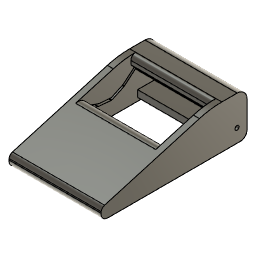
kb46sp_r1 (Autodesk Fusion 360 design; units mm, degrees)
Autodesk Fusion 360 part; units mm, degrees
sketch "Sketch10" plane through (0, 0, 0) normal (1, 0, 0) x (0, 1, 0)
  line L0 (-37.4967, 30.9274) -> (-28.9967, 45.6498)
  line L1 (-28.9967, 45.6498) -> (28.9967, 45.6498)
  line L2 (-37.4967, 30.9274) -> (-20.4967, 30.9274) construction
  line L3 (37.4967, 30.9274) -> (55.3527, 0)
  line L4 (37.4967, 30.9274) -> (28.9967, 45.6498)
  line L5 (-37.4967, 30.9274) -> (-55.3527, 0)
  line L6 (-37.4967, 30.9274) -> (-20.4967, 30.9274) construction
  line L7 (-28.9967, 45.6498) -> (28.9967, 45.6498)
  line L8 (-37.4967, 30.9274) -> (-28.9967, 45.6498)
  line L9 (-37.4967, 30.9274) -> (-55.3527, 0)
  line L10 (37.4967, 30.9274) -> (55.3527, 0)
  line L11 (37.4967, 30.9274) -> (28.9967, 45.6498)
  line L12 (55.3527, 0) -> (-55.3527, 0)
  line L13 (0, 0) -> (0, 45.6498) construction
  dimension "d62" = 17
  dimension "d63" = 60
  dimension "d64" = 17
  dimension "d66" = 17
  dimension "d67" = 60
  dimension "d68" = 17
  constraint horizontal L2
  constraint horizontal L6
  constraint horizontal L12
  constraint midpoint L12 L13.start
  constraint midpoint L7 L13.end
  constraint perpendicular L7 L13
  measures "d62" distance of L1.end L3.start
  measures "d63" angle of L2 L8
  measures "d64" distance of L0.start L0.end
  measures "d66" distance of L1.end L3.start
  measures "d67" angle of L0 L6
  measures "d68" distance of L0.end L0.start
sketch "Sketch12" plane through (0, 0, 0) normal (1, 0, 0) x (0, 1, 0)
  line L0 (0, 0) -> (-220, 0)
  line L1 (-55, 65) -> (0, 65)
  line L2 (0, 65) -> (0, 0)
  line L3 (-55, 65) -> (-218.051, 17.5974)
  line L4 (-220, 0) -> (-218.051, 17.5974)
  dimension "d39" = 65
  dimension "d41" = 55
  dimension "d197" = 220
  constraint vertical L2
  constraint coincident L0.start L2.end
  constraint horizontal L0
  measures "d39" distance of L0 L1
  measures "d41" distance of L1.start L1.end
  measures "d197" distance of L0.start L0.end
extrude "Extrude6" add sketch "Sketch12" along normal mid plane 138 makes body 1
sketch "Sketch14" plane through (0, 0, 0) normal (1, 0, 0) x (0, 1, 0)
  line L0 (-18.4009, 19.9024) -> (0, 14.9719)
  line L1 (-0.9059, 11.5911) -> (-19.3068, 16.5216)
  line L2 (-18.4009, 19.9024) -> (-40.8742, 32.8774)
  line L3 (-43.5589, 34.4274) -> (-45.3089, 31.3963)
  line L4 (-42.6242, 29.8463) -> (-20.1509, 16.8713)
  line L5 (18.4009, 19.9024) -> (0, 14.9719)
  line L6 (0.9059, 11.5911) -> (19.3068, 16.5216)
  line L7 (40.8742, 32.8774) -> (18.4009, 19.9024)
  line L8 (45.3089, 31.3963) -> (43.5589, 34.4274)
  line L9 (20.1509, 16.8713) -> (42.6242, 29.8463)
  line L10 (0, 14.9719) -> (0, 0) construction
  line L11 (20.1509, 16.8713) -> (19.3068, 16.5216)
  line L12 (0.9059, 11.5911) -> (0.4529, 11.4697)
  line L13 (0.4529, 11.4697) -> (-0.9059, 11.5911)
  line L14 (-19.3068, 16.5216) -> (-20.1509, 16.8713)
  arc A0 (-40.8742, 32.8774) -> (-43.5589, 34.4274) centre (-42.2166, 33.6524) ccw
  arc A1 (-45.3089, 31.3963) -> (-42.6242, 29.8463) centre (-43.9666, 30.6213) ccw
  arc A2 (43.5589, 34.4274) -> (40.8742, 32.8774) centre (42.2166, 33.6524) ccw
  arc A3 (42.6242, 29.8463) -> (45.3089, 31.3963) centre (43.9666, 30.6213) ccw
  dimension "d104" = 3.1
  dimension "d105" = 3.1
  dimension "d106" = 3.1
  dimension "d107" = 3.1
  constraint parallel L0 L1
  constraint perpendicular L2 L3
  constraint parallel L2 L4
  constraint parallel L5 L6
  constraint parallel L7 L9
  constraint vertical L10
  measures "d104" diameter of A2
  measures "d105" diameter of A3
  measures "d106" diameter of A0
  measures "d107" diameter of A1
extrude "Extrude9" add sketch "Sketch14" along normal mid plane 130 separate body makes body 2
extrude "Extrude10" add sketch "Sketch10" along normal mid plane 120 separate body makes body 3
move_body "Move20" bodies 3 2 to x (1, 0, 0) y (0, 0.984808, 0.173648) z (0, -0.173648, 0.984808) at (0, -0.8409, 9.6119)
move_body "Move21" bodies 3 2 to x (1, 0, 0) y (0, 1, 0) z (0, 0, 1) at (0, -70.951, 0)
sketch "Sketch16" plane through (0, 0, 0) normal (1, 0, 0) x (0, 1, 0)
  line L0 (-45, 71.5447) -> (-108.2752, 71.5447)
  line L1 (-40.2353, 46.5806) -> (-37.2477, 49.0875)
  line L2 (-34.873, 51.0801) -> (-32.6233, 48.399)
  line L3 (-34.998, 46.4063) -> (-37.9856, 43.8995)
  line L4 (-113.4492, 38.646) -> (-115.1593, 33.9475)
  line L5 (-120.6684, 35.9493) -> (-121.8644, 32.6634)
  line L6 (-118.9514, 31.6031) -> (-116.3564, 30.6586)
  line L7 (-10, 40.0693) -> (-10, 15)
  line L8 (-10, 15) -> (-35, 15)
  line L9 (-37.9856, 43.8995) -> (-34.998, 46.4063)
  line L10 (-37.2477, 49.0875) -> (-40.2353, 46.5806)
  line L11 (-118.9514, 31.6031) -> (-116.3564, 30.6586)
  line L12 (-34.7716, 40.0693) -> (-37.9856, 43.8995)
  line L13 (-45, 71.5447) -> (-45, 52.2589)
  line L14 (-40.2353, 46.5806) -> (-45, 52.2589)
  line L15 (-10, 40.0693) -> (-34.7716, 40.0693)
  line L16 (-119.7766, 21.2617) -> (-144.7766, 21.2617)
  line L17 (-116.3564, 30.6586) -> (-119.7766, 21.2617)
  line L18 (-144.7766, 4.9542) -> (-148.678, 4.9542)
  line L19 (-151.7766, 5) -> (-151.7766, 0)
  line L20 (-144.7766, 21.2617) -> (-144.7766, 4.9542)
  line L21 (-35, 5) -> (-31.1, 5)
  line L22 (-28, 5) -> (-28, 0)
  line L23 (-35, 15) -> (-35, 5)
  line L24 (-151.7766, 0) -> (-28, 0)
  line L25 (-117.7543, 34.892) -> (-115.1593, 33.9475)
  arc A0 (-148.678, 4.9542) -> (-151.7766, 4.8729) centre (-150.2279, 4.9365) ccw
  arc A1 (-28, 5) -> (-31.1, 5) centre (-29.55, 5) ccw
  arc A2 (-34.998, 46.4063) -> (-32.6233, 48.399) centre (-33.8106, 47.4027) ccw
  arc A3 (-34.873, 51.0801) -> (-37.2477, 49.0875) centre (-36.0604, 50.0838) ccw
  arc A4 (-117.7543, 34.892) -> (-120.6684, 35.9493) centre (-119.2119, 35.4192) ccw
  arc A5 (-121.8644, 32.6634) -> (-118.9514, 31.6031) centre (-120.4079, 32.1332) ccw
  line L26 (-113.4492, 38.646) -> (-121.4288, 48.1557)
  line L27 (-113.4492, 38.646) -> (-103.1508, 38.646) construction
  line L28 (-121.4288, 48.1557) -> (-108.2752, 71.5447)
  dimension "d74" = 10
  dimension "d75" = 5
  dimension "d77" = 15
  dimension "d78" = 25
  dimension "d79" = 10
  dimension "d81" = 7
  dimension "d82" = 5
  dimension "d83" = 7
  dimension "d84" = 5
  dimension "d110" = 25
  dimension "d118" = 3.1
  dimension "d119" = 3.1
  dimension "d120" = 3.1
  dimension "d121" = 3.1
  dimension "d122" = 3.1
  dimension "d123" = 3.1
  dimension "d198" = 130
  dimension "d199" = 5
  dimension "d200" = 3.5
  dimension "d201" = 3.5
  constraint coincident L2.end A2.end
  constraint coincident L5.end A5.start
  constraint perpendicular L7 L8
  constraint horizontal L0
  constraint perpendicular L3 L12
  constraint vertical L13
  constraint perpendicular L2 L9
  constraint perpendicular L2 L10
  constraint perpendicular L1 L14
  constraint perpendicular L7 L15
  constraint perpendicular L6 L17
  constraint perpendicular L18 L20
  constraint perpendicular L21 L23
  constraint perpendicular L22 L24
  constraint horizontal L16
  constraint coincident L19.start A0
  constraint perpendicular L4 L25
  constraint coincident L19 A0.end
  constraint vertical L20
  constraint vertical L19
  constraint vertical L7
  constraint vertical L23
  constraint vertical L22
  constraint horizontal L27
  constraint equal L6 L25
  constraint parallel L4 L17
  measures "d74" distance of origin L7
  measures "d75" distance of L3.end L12.start
  measures "d77" distance of origin L8
  measures "d78" distance of L7.end L8.end
  measures "d79" distance of L6.end L16.start
  measures "d81" horizontal distance of L18.start L19.start
  measures "d82" distance of L19.start L19.end
  measures "d83" distance of L21.start L22.start
  measures "d84" distance of L22.start L22.end
  measures "d110" horizontal distance of L16.start L16.end
  measures "d118" diameter of A1
  measures "d119" diameter of A0
  measures "d120" diameter of A3
  measures "d121" diameter of A2
  measures "d122" diameter of A4
  measures "d123" diameter of A5
  measures "d198" angle of L26 L27
  measures "d199" distance of L4.end L4.start
  measures "d200" distance of L6 L25
  measures "d201" distance of L3 L10
extrude "Extrude11" cut sketch "Sketch16" along normal mid plane 120 bodies 1
combine "Combine1" operation cut target body 1 tool bodies 2
fillet "Fillet1" radius 120 2 edges at (64.5, -55, 65) (-64.5, -55, 65) on bodies 1
fillet "Fillet2" radius 7 1 edges at (0, -45, 64.7904) on bodies 1
fillet "Fillet3" radius 7 1 edges at (0, -218.051, 17.5974) on bodies 1
fillet "Fillet4" radius 10 1 edges at (0, -220, 0) on bodies 1
fillet "Fillet5" radius 15 1 edges at (0, 0, 65) on bodies 1
fillet "Fillet6" radius 13 1 edges at (0, -119.764, 46.1716) on bodies 1
fillet "Fillet7" radius 10 1 edges at (0, 0, 0) on bodies 1
fillet "Fillet8" radius 3 2 edges at (0, -28, 0) (0, -151.7766, 0) on bodies 1
extrude "Extrude12" add sketch "Sketch14" along normal mid plane 130 separate body makes body 4
move_body "Move22" bodies 4 to x (1, 0, 0) y (0, 0.984808, 0.173648) z (0, -0.173648, 0.984808) at (0, 1.3002, 8.0781)
move_body "Move23" bodies 4 to x (1, 0, 0) y (0, 1, 0) z (0, 0, 1) at (65, -73.0932, 1.5308)
move_body "Move24" bodies 4 to x (1, 0, 0) y (0, 1, 0) z (0, 0, 1) at (-65, 0, 0)
combine "Combine2" operation cut target body 1 tool bodies 4
sketch "Sketch19" plane through (0, 0, 0) normal (1, 0, 0) x (0, 1, 0)
  line L0 (-134.6766, 21.2617) -> (-131.8766, 21.2617)
  line L1 (-128.7766, 21.2617) -> (-128.7766, 31.2617)
  line L2 (-131.8766, 31.2617) -> (-134.6766, 31.2617)
  line L3 (-137.7766, 31.2617) -> (-137.7766, 21.2617)
  arc A0 (-134.6766, 31.2617) -> (-137.7766, 31.2617) centre (-136.2266, 31.2617) ccw
  arc A1 (-128.7766, 31.2617) -> (-131.8766, 31.2617) centre (-130.3266, 31.2617) ccw
  arc A2 (-137.7766, 21.2617) -> (-134.6766, 21.2617) centre (-136.2266, 21.2617) ccw
  arc A3 (-131.8766, 21.2617) -> (-128.7766, 21.2617) centre (-130.3266, 21.2617) ccw
  line L4 (-10, 40.0693) -> (-34.7716, 40.0693) construction
  line L5 (-26, 40.0693) -> (-26, 55.0693)
  line L6 (-22.9, 55.0693) -> (-20.1, 55.0693)
  line L7 (-17, 55.0693) -> (-17, 40.0693)
  arc A4 (-22.9, 55.0693) -> (-26, 55.0693) centre (-24.45, 55.0693) ccw
  arc A5 (-17, 55.0693) -> (-20.1, 55.0693) centre (-18.55, 55.0693) ccw
  arc A6 (-20.1, 40.0693) -> (-17, 40.0693) centre (-18.55, 40.0693) ccw
  arc A7 (-26, 40.0693) -> (-22.9, 40.0693) centre (-24.45, 40.0693) ccw
  line L8 (-22.9, 40.0693) -> (-20.1, 40.0693)
  line L9 (0, 0) -> (-220, 0) construction
  line L10 (-205, 0) -> (-205, 41.8728) construction
  line L11 (-205, 0) -> (-196, 0)
  line L12 (-196, 0) -> (-196, 15)
  line L13 (-199.1, 15) -> (-201.9, 15)
  line L14 (-205, 15) -> (-205, 0)
  arc A8 (-196, 15) -> (-199.1, 15) centre (-197.55, 15) ccw
  arc A9 (-201.9, 15) -> (-205, 15) centre (-203.45, 15) ccw
  line L15 (-21, 0) -> (-12, 0)
  line L16 (-12, 0) -> (-12, 10)
  line L17 (-15.1, 10) -> (-17.9, 10)
  line L18 (-21, 10) -> (-21, 0)
  arc A10 (-17.9, 10) -> (-21, 10) centre (-19.45, 10) ccw
  arc A11 (-12, 10) -> (-15.1, 10) centre (-13.55, 10) ccw
  point P0 (-10, 40.0693)
  point P1 (-144.7766, 21.2617)
  dimension "d124" = 9
  dimension "d125" = 10
  dimension "d126" = 3.1
  dimension "d127" = 3.1
  dimension "d128" = 3.1
  dimension "d130" = 3.1
  dimension "d152" = 9
  dimension "d153" = 15
  dimension "d154" = 3.1
  dimension "d155" = 3.1
  dimension "d156" = 3.1
  dimension "d157" = 3.1
  dimension "d158" = 15
  dimension "d159" = 9
  dimension "d160" = 15
  dimension "d161" = 3.1
  dimension "d162" = 3.1
  dimension "d165" = 9
  dimension "d166" = 10
  dimension "d167" = 12
  dimension "d168" = 3.1
  dimension "d169" = 3.1
  dimension "d172" = 7
  dimension "d173" = 7
  constraint horizontal L0
  constraint vertical L1
  constraint horizontal L2
  constraint vertical L3
  constraint vertical L5
  constraint horizontal L6
  constraint vertical L7
  constraint coincident L7.end A6.end
  constraint coincident L4 A6.start
  constraint coincident L4 A7.end
  constraint coincident L9 L10.start
  constraint perpendicular L9 L10
  constraint horizontal L11
  constraint vertical L12
  constraint horizontal L13
  constraint vertical L14
  constraint horizontal L15
  constraint vertical L16
  constraint horizontal L17
  constraint vertical L18
  constraint coincident L9 L15.start
  measures "d124" distance of L3.end L1.start
  measures "d125" distance of L3.end L3.start
  measures "d126" diameter of A0
  measures "d127" diameter of A1
  measures "d128" diameter of A2
  measures "d130" diameter of A3
  measures "d152" distance of L7.end L5.start
  measures "d153" distance of L7.end L7.start
  measures "d154" diameter of A5
  measures "d155" diameter of A4
  measures "d156" diameter of A7
  measures "d157" diameter of A6
  measures "d158" distance of L9.end L10
  measures "d159" distance of L10.start L11.end
  measures "d160" distance of L10.start L14.start
  measures "d161" diameter of A9
  measures "d162" diameter of A8
  measures "d165" distance of L15.start L15.end
  measures "d166" distance of L15.start L18.start
  measures "d167" distance of L16 L9.start
  measures "d168" diameter of A11
  measures "d169" diameter of A10
  measures "d172" distance of L7 P0
  measures "d173" distance of L3 P1
extrude "Extrude13" cut sketch "Sketch19" along normal mid plane 130 bodies 1
sketch "Sketch21" plane through (0, 0, 0) normal (0, 1, 0) x (1, 0, 0)
  line L0 (-54, -22.1) -> (-54, -17) construction
  line L1 (-54, -17) -> (-42, -17)
  line L2 (-42, -17) -> (-42, -22.2)
  line L3 (-42, -22.2) -> (-54, -22.2)
  line L4 (-54, -22.2) -> (-54, -17)
  point P0 (-60, -15)
  dimension "d183" = 2
  dimension "d184" = 6
  dimension "d185" = 12
  dimension "d186" = 5.2
  constraint horizontal L1
  constraint vertical L2
  constraint horizontal L3
  constraint vertical L4
  measures "d183" vertical distance of L0.end P0
  measures "d184" horizontal distance of L0.end P0
  measures "d185" distance of L0.end L1.end
  measures "d186" distance of L0.end L3.end
extrude "Extrude14" cut sketch "Sketch21" against normal blind 30 bodies 1
sketch "Sketch23" plane through (0, 0, 0) normal (1, 0, 0) x (0, 1, 0)
  line L0 (-12, 17) -> (-18, 17) construction
  line L1 (-18, 17) -> (-18, 23) construction
  line L2 (-18, 23) -> (-12, 23) construction
  line L3 (-12, 23) -> (-12, 17) construction
  line L4 (-12, 23) -> (-18, 17) construction
  line L5 (-12, 17) -> (-18, 23) construction
  circle A0 centre (-15, 20) radius 3.1
  point P0 (-10, 15)
  dimension "d189" = 6
  dimension "d190" = 6
  dimension "d191" = 2
  dimension "d192" = 2
  dimension "d194" = 6.2
  constraint horizontal L0
  constraint vertical L1
  constraint horizontal L2
  constraint vertical L3
  constraint midpoint L4 A0.centre
  measures "d189" distance of L0.start L0.end
  measures "d190" distance of L0.start L2.end
  measures "d191" horizontal distance of L0.start P0
  measures "d192" vertical distance of L0.start P0
  measures "d194" diameter of A0
extrude "Extrude15" cut sketch "Sketch23" along normal through all bodies 1
sketch "Sketch24" plane through (0, 0, 0) normal (1, 0, 0) x (0, 1, 0)
  line L0 (-119.7766, 21.2617) -> (-144.7766, 21.2617) construction
  line L1 (-121.8644, 32.6634) -> (-125.7438, 21.2617)
  line L2 (-116.3564, 30.6586) -> (-119.7766, 21.2617)
  line L3 (-121.8644, 32.6634) -> (-116.3564, 30.6586)
  line L4 (-119.7766, 21.2617) -> (-125.7438, 21.2617)
  line L5 (-10, 40.0693) -> (-34.7716, 40.0693) construction
  arc A0 (-34.998, 46.4063) -> (-32.6233, 48.399) centre (-33.8106, 47.4027) ccw construction
  line L6 (-34.873, 51.0801) -> (-32.6233, 48.399) construction
  line L7 (-32.6233, 48.399) -> (-25.6338, 40.0693)
  line L8 (-34.998, 46.4063) -> (-37.9856, 43.8995) construction
  line L9 (-34.7716, 40.0693) -> (-37.9856, 43.8995)
  line L10 (-32.6233, 48.399) -> (-37.9856, 43.8995)
  line L11 (-34.7716, 40.0693) -> (-25.6338, 40.0693)
  point P0 (-121.8644, 32.6634)
  point P1 (-116.3564, 30.6586)
  point P2 (-32.6233, 48.399)
  point P3 (-37.9856, 43.8995)
  constraint coincident P0 L1.start
  constraint coincident L0 L1.end
  constraint coincident P1 L2.start
  constraint coincident L0.start L2.end
  constraint parallel L0 L4
  constraint coincident P2 A0.end
  constraint coincident L5 L7.end
  constraint tangent A0 L7
  constraint parallel L6 L7
  constraint coincident L5.end L9.start
  constraint coincident P3 L8.end
extrude "Extrude16" cut sketch "Sketch24" along normal mid plane 8 bodies 1
hidden bodies 3
